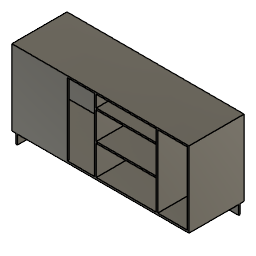
Front Counter - R2 (Autodesk Fusion 360 design; units mm, degrees)
Autodesk Fusion 360 part; units mm, degrees
sketch "Sketch1" plane through (0, 0, 0) normal (0, 0, 1) x (1, 0, 0)
  line L0 (0, 0) -> (178, 0)
  line L1 (178, 0) -> (178, 55.5)
  line L2 (178, 55.5) -> (0, 55.5)
  line L3 (0, 55.5) -> (0, 0)
  dimension "d1" = 178
  dimension "d2" = 55.5
  constraint horizontal L0
  constraint vertical L1
  constraint horizontal L2
  constraint vertical L3
  constraint coincident L0.start L3.end
  measures "d1" distance of L0.start L0.end
  measures "d2" distance of L0.start L2.end
extrude "Extrude1" add sketch "Sketch1" along normal blind 76
sketch "Sketch2" plane through (0, 0, 0) normal (0, -1, 0) x (1, 0, 0)
  line L0 (0, 0) -> (178, 0)
  line L1 (178, 0) -> (178, 76)
  line L2 (178, 76) -> (0, 76)
  line L3 (0, 76) -> (0, 0)
  line L4 (0, 76) -> (1.6, 76)
  line L5 (1.6, 76) -> (1.6, 74.4)
  line L6 (1.6, 74.4) -> (176.4, 74.4)
  line L7 (176.4, 74.4) -> (176.4, 1.9)
  line L8 (176.4, 1.9) -> (1.6, 1.9)
  line L9 (1.6, 1.9) -> (1.6, 74.4)
  dimension "d5" = 1.6
  dimension "d6" = 1.6
  dimension "d7" = 174.8
  dimension "d8" = 72.5
  constraint coincident L2.end L3.start
  constraint horizontal L4
  constraint vertical L5
  constraint horizontal L6
  constraint vertical L7
  constraint horizontal L8
  constraint vertical L9
  measures "d5" distance of L2.end L4.end
  measures "d6" distance of L4.end L5.end
  measures "d7" distance of L5.end L6.end
  measures "d8" distance of L5.end L8.end
extrude "Extrude2" cut sketch "Sketch2" against normal blind 54.5 contours L6 L7 L8 L9
sketch "Sketch3" plane through (0, 0, 0) normal (0, -1, 0) x (1, 0, 0)
  line L0 (176.4, 74.4) -> (176.4, 1.9)
  line L1 (176.4, 1.9) -> (1.6, 1.9)
  line L2 (1.6, 1.9) -> (1.6, 74.4)
  line L3 (1.6, 74.4) -> (176.4, 74.4)
  line L4 (0, 0) -> (178, 0)
  line L5 (178, 0) -> (178, 76)
  line L6 (178, 76) -> (0, 76)
  line L7 (0, 76) -> (0, 0)
  line L8 (1.6, 74.4) -> (55.9, 74.4)
  line L9 (55.9, 74.4) -> (55.9, 1.9)
  line L10 (55.9, 1.9) -> (1.6, 1.9)
  line L11 (1.6, 1.9) -> (1.6, 74.4)
  dimension "d11" = 54.3
  constraint horizontal L8
  constraint vertical L9
  constraint horizontal L10
  constraint vertical L11
  constraint coincident L2.end L3.start
  measures "d11" distance of L2.end L8.end
extrude "Extrude3" add sketch "Sketch3" against normal blind 1.6 contours L1 L2 L3 L8 L9 L10 L11
sketch "Sketch4" plane through (0, 0, 0) normal (0, -1, 0) x (1, 0, 0)
  line L0 (176.4, 74.4) -> (176.4, 1.9)
  line L1 (176.4, 1.9) -> (55.9, 1.9)
  line L2 (55.9, 1.9) -> (55.9, 74.4)
  line L3 (55.9, 74.4) -> (176.4, 74.4)
  line L4 (0, 0) -> (178, 0)
  line L5 (178, 0) -> (178, 76)
  line L6 (178, 76) -> (0, 76)
  line L7 (0, 76) -> (0, 0)
  line L8 (55.9, 74.4) -> (83.2, 74.4)
  line L9 (83.2, 74.4) -> (84.8, 74.4)
  line L10 (84.8, 74.4) -> (84.8, 1.9)
  line L11 (84.8, 1.9) -> (83.2, 1.9)
  line L12 (83.2, 1.9) -> (83.2, 74.4)
  dimension "d14" = 27.3
  dimension "d15" = 1.6
  constraint coincident L2.end L3.start
  constraint perpendicular L2 L8
  constraint horizontal L9
  constraint vertical L10
  constraint horizontal L11
  constraint vertical L12
  measures "d14" distance of L2.end L8.end
  measures "d15" distance of L8.end L9.end
extrude "Extrude4" add sketch "Sketch4" against normal blind 54.5 contours L1 L3 L9 L10 L11 L12
sketch "Sketch5" plane through (0, 0, 0) normal (0, -1, 0) x (1, 0, 0)
  line L0 (84.8, 74.4) -> (176.4, 74.4)
  line L1 (176.4, 74.4) -> (176.4, 1.9)
  line L2 (176.4, 1.9) -> (84.8, 1.9)
  line L3 (84.8, 1.9) -> (84.8, 74.4)
  line L4 (83.2, 74.4) -> (83.2, 1.9)
  line L5 (83.2, 1.9) -> (55.9, 1.9)
  line L6 (55.9, 1.9) -> (55.9, 74.4)
  line L7 (55.9, 74.4) -> (83.2, 74.4)
  line L8 (0, 0) -> (178, 0)
  line L9 (178, 0) -> (178, 76)
  line L10 (178, 76) -> (0, 76)
  line L11 (0, 76) -> (0, 0)
  line L12 (84.8, 74.4) -> (84.8, 62.4)
  line L13 (84.8, 62.4) -> (144.8, 62.4)
  line L14 (144.8, 62.4) -> (144.8, 60.8)
  line L15 (144.8, 60.8) -> (84.8, 60.8)
  line L16 (84.8, 60.8) -> (84.8, 62.4)
  line L17 (84.8, 60.8) -> (84.8, 33.3)
  line L18 (84.8, 33.3) -> (144.8, 33.3)
  line L19 (144.8, 33.3) -> (144.8, 31.7)
  line L20 (144.8, 31.7) -> (84.8, 31.7)
  line L21 (84.8, 31.7) -> (84.8, 33.3)
  line L22 (144.8, 60.8) -> (144.8, 33.3)
  line L23 (144.8, 31.7) -> (144.8, 1.9)
  dimension "d18" = 12
  dimension "d19" = 60
  dimension "d20" = 1.6
  dimension "d21" = 27.5
  dimension "d22" = 60
  dimension "d23" = 1.6
  constraint coincident L0.start L3.end
  constraint perpendicular L7 L12
  constraint horizontal L13
  constraint vertical L14
  constraint horizontal L15
  constraint vertical L16
  constraint perpendicular L15 L17
  constraint horizontal L18
  constraint vertical L19
  constraint horizontal L20
  constraint vertical L21
  constraint coincident L2 L23.end
  constraint perpendicular L2 L23
  measures "d18" distance of L0.start L12.end
  measures "d19" distance of L12.end L13.end
  measures "d20" distance of L12.end L15.end
  measures "d21" distance of L15.end L17.end
  measures "d22" distance of L17.end L18.end
  measures "d23" distance of L17.end L20.end
extrude "Extrude5" add sketch "Sketch5" against normal blind 54.5 contours L3 L13 L14 L15 L16 | L3 L18 L19 L20 L21
sketch "Sketch6" plane through (0, 0, 0) normal (0, -1, 0) x (1, 0, 0)
  line L0 (84.8, 74.4) -> (176.4, 74.4)
  line L1 (176.4, 74.4) -> (176.4, 1.9)
  line L2 (176.4, 1.9) -> (84.8, 1.9)
  line L3 (84.8, 1.9) -> (84.8, 31.7)
  line L4 (84.8, 31.7) -> (144.8, 31.7)
  line L5 (144.8, 31.7) -> (144.8, 33.3)
  line L6 (144.8, 33.3) -> (84.8, 33.3)
  line L7 (84.8, 33.3) -> (84.8, 60.8)
  line L8 (84.8, 60.8) -> (144.8, 60.8)
  line L9 (144.8, 60.8) -> (144.8, 62.4)
  line L10 (144.8, 62.4) -> (84.8, 62.4)
  line L11 (84.8, 62.4) -> (84.8, 74.4)
  line L12 (83.2, 74.4) -> (83.2, 1.9)
  line L13 (83.2, 1.9) -> (55.9, 1.9)
  line L14 (55.9, 1.9) -> (55.9, 74.4)
  line L15 (55.9, 74.4) -> (83.2, 74.4)
  line L16 (0, 0) -> (178, 0)
  line L17 (178, 0) -> (178, 76)
  line L18 (178, 76) -> (0, 76)
  line L19 (0, 76) -> (0, 0)
  line L20 (176.4, 74.4) -> (146.7, 74.4)
  line L21 (146.7, 74.4) -> (145.1, 74.4)
  line L22 (145.1, 74.4) -> (145.1, 1.9)
  line L23 (145.1, 1.9) -> (146.7, 1.9)
  line L24 (146.7, 1.9) -> (146.7, 74.4)
  dimension "d26" = 29.7
  dimension "d27" = 1.6
  constraint coincident L0.end L1.start
  constraint perpendicular L1 L20
  constraint horizontal L21
  constraint vertical L22
  constraint horizontal L23
  constraint vertical L24
  measures "d26" distance of L0.end L20.end
  measures "d27" distance of L20.end L21.end
extrude "Extrude6" add sketch "Sketch6" against normal blind 54.5 contours L0 L2 L21 L22 L23 L24
sketch "Sketch7" plane through (0, 0, 0) normal (0, 0, -1) x (1, 0, 0)
  line L0 (0, 0) -> (0, -55.5)
  line L1 (0, -55.5) -> (178, -55.5)
  line L2 (178, -55.5) -> (178, 0)
  line L3 (178, 0) -> (0, 0)
  line L4 (0, 0) -> (4, 0)
  line L5 (4, 0) -> (5.6, 0)
  line L6 (5.6, 0) -> (5.6, -51.5)
  line L7 (5.6, -51.5) -> (4, -51.5)
  line L8 (4, -51.5) -> (4, 0)
  line L9 (4, -51.5) -> (178, -51.5)
  line L10 (178, -51.5) -> (178, -49.9)
  line L11 (178, -49.9) -> (4, -49.9)
  line L12 (4, -49.9) -> (4, -51.5)
  dimension "d30" = 4
  dimension "d31" = 1.6
  dimension "d32" = 51.5
  dimension "d33" = 1.6
  constraint coincident L0.start L3.end
  constraint perpendicular L0 L4
  constraint horizontal L5
  constraint vertical L6
  constraint horizontal L7
  constraint vertical L8
  constraint horizontal L9
  constraint vertical L10
  constraint horizontal L11
  constraint vertical L12
  measures "d30" distance of L0.start L4.end
  measures "d31" distance of L4.end L5.end
  measures "d32" distance of L4.end L7.end
  measures "d33" distance of L7.end L11.end
extrude "Extrude7" add sketch "Sketch7" along normal blind 9.5 contours L3 L5 L6 L8 L11 | L6 L7 L8 L9 L11 L12 | L2 L6 L9 L10 L11
